knekelbeen_nek (Autodesk Fusion 360 design; units mm, degrees)
part number: 2026-10-25-00-56-09-742
part number: 2026-10-25-00-59-24-102
part number: 2026-10-25-00-59-58-262
part number: 2026-10-25-01-19-24-813
part number: 2026-10-25-01-20-03-116
part number: 2026-10-25-01-20-03-267
part number: 2026-10-25-01-20-03-368
part number: 2026-10-25-01-20-03-475
part number: 2026-10-25-01-20-03-508
part number: 2026-10-26-13-14-03-304
part number: 2026-10-26-13-14-24-246
Autodesk Fusion 360 part; units mm, degrees
sketch "Base outline" plane through (0, 0, 0) normal (0, 0, 1) x (1, 0, 0) in component "Base"
  circle A0 centre (0, 0) radius 52
  line L0 (0, -27) -> (81, -27)
  line L1 (81, -27) -> (81, 27)
  line L2 (81, 27) -> (0, 27)
  line L3 (0, 27) -> (0, -27)
extrude "Base plate" add sketch "Base outline" along normal blind 3 makes body 1 in component "Base"
ref_plane "WorkPlane1" through (0, 0, 3) normal (0, 0, 1) x (1, 0, 0) in component "Base"
sketch "Back wall" plane through (0, 0, 3) normal (0, 0, 1) x (1, 0, 0) in component "Base"
  line L0 (70.5, -13.9) -> (78, -13.9)
  line L1 (78, -13.9) -> (78, 24.6)
  line L2 (78, 24.6) -> (70.5, 24.6)
  line L3 (70.5, 24.6) -> (70.5, -13.9)
extrude "Back wall (1)" add sketch "Back wall" along normal blind 26.5 bodies 1 in component "Base"
ref_plane "WorkPlane2" through (0, 0, 17.5) normal (0, 0, 1) x (1, 0, 0) in component "Base"
sketch "Corbels" plane through (0, 0, 17.5) normal (0, 0, 1) x (1, 0, 0) in component "Base"
  line L0 (61, -11.9) -> (72, -11.9)
  line L1 (72, -11.9) -> (72, -6.2)
  line L2 (72, -6.2) -> (61, -6.2)
  line L3 (61, -6.2) -> (61, -11.9)
  line L4 (61, 16.9) -> (72, 16.9)
  line L5 (72, 16.9) -> (72, 22.6)
  line L6 (72, 22.6) -> (61, 22.6)
  line L7 (61, 22.6) -> (61, 16.9)
extrude "Corbels (1)" add sketch "Corbels" along normal blind 12 separate body makes body 2 at (68.3333, -6.2, 21.5) makes body 3 at (68.3333, 22.6, 21.5) in component "Base"
chamfer "45 deg underside" distance 9.5 angle 45 2 edges at (61, -9.05, 17.5) (61, 19.75, 17.5) tangent chain off on bodies 2 3 in component "Base"
combine "Join corbels" operation add target body 1 tool bodies 2 3 in component "Base"
ref_plane "WorkPlane3" through (0, 0, 29.5) normal (0, 0, 1) x (1, 0, 0) in component "Base"
sketch "M2 inserts servo tabs" plane through (0, 0, 29.5) normal (0, 0, 1) x (1, 0, 0) in component "Base"
  circle A0 centre (64, -8.5) radius 1.5
  circle A1 centre (64, 19.2) radius 1.5
  dimension "d23" = 3
  dimension "d24" = 3
  measures "d23" diameter of A0
  measures "d24" diameter of A1
extrude "M2 insert holes" cut sketch "M2 inserts servo tabs" against normal blind 4 bodies 1 in component "Base"
sketch "Lazy susan holes" plane through (0, 0, 0) normal (0, 0, 1) x (1, 0, 0) in component "Base"
  circle A0 centre (-29, -29) radius 2.25
  circle A1 centre (-29, 29) radius 2.25
  circle A2 centre (29, -29) radius 2.25
  circle A3 centre (29, 29) radius 2.25
extrude "Lazy susan holes (1)" cut sketch "Lazy susan holes" along normal blind 3 bodies 1 in component "Base"
sketch "Lazy susan countersinks" plane through (0, 0, 0) normal (0, 0, 1) x (1, 0, 0) in component "Base"
  circle A0 centre (-29, -29) radius 4.3
  circle A1 centre (-29, 29) radius 4.3
  circle A2 centre (29, -29) radius 4.3
  circle A3 centre (29, 29) radius 4.3
extrude "Countersinks M4" cut sketch "Lazy susan countersinks" along normal blind 2.05 draft -45 bodies 1 in component "Base"
sketch "Floor screw holes" plane through (0, 0, 0) normal (0, 0, 1) x (1, 0, 0) in component "Base"
  circle A0 centre (46.5, 0) radius 1.7
  circle A1 centre (-46.5, 0) radius 1.7
  circle A2 centre (0, 46.5) radius 1.7
  circle A3 centre (0, -46.5) radius 1.7
extrude "Floor screw holes (1)" cut sketch "Floor screw holes" along normal blind 3 bodies 1 in component "Base"
sketch "Floor screw countersinks" plane through (0, 0, 3) normal (0, 0, 1) x (1, 0, 0) in component "Base"
  circle A0 centre (46.5, 0) radius 3.3
  circle A1 centre (-46.5, 0) radius 3.3
  circle A2 centre (0, 46.5) radius 3.3
  circle A3 centre (0, -46.5) radius 3.3
extrude "Floor countersinks" cut sketch "Floor screw countersinks" against normal blind 1.6 draft -45 bodies 1 in component "Base"
sketch "Centre + arm screw access" plane through (0, 0, 0) normal (0, 0, 1) x (1, 0, 0) in component "Base"
  circle A0 centre (0, 0) radius 15
  circle A1 centre (64, 0) radius 3.5
extrude "Centre + access holes" cut sketch "Centre + arm screw access" along normal blind 3 bodies 1 in component "Base"
ref_plane "WorkPlane1" through (0, 0, 11) normal (0, 0, 1) x (1, 0, 0) in component "Cap"
ref_plane "WorkPlane2" through (0, 0, 15) normal (0, 0, 1) x (1, 0, 0) in component "Cap"
sketch "Cap outline" plane through (0, 0, 11) normal (0, 0, 1) x (1, 0, 0) in component "Cap"
  circle A0 centre (0, 0) radius 48
  line L0 (30, -7) -> (57, -7)
  line L1 (57, -7) -> (57, 7)
  line L2 (57, 7) -> (30, 7)
  line L3 (30, 7) -> (30, -7)
extrude "Cap plate" add sketch "Cap outline" along normal blind 4 separate body makes body 4 in component "Cap"
sketch "Wire hole" plane through (0, 0, 11) normal (0, 0, 1) x (1, 0, 0) in component "Cap"
  circle A0 centre (0, 0) radius 7
extrude "Wire hole (1)" cut sketch "Wire hole" along normal blind 4 bodies 4 in component "Cap"
sketch "Ball track clearance" plane through (0, 0, 11) normal (0, 0, 1) x (1, 0, 0) in component "Cap"
  circle A0 centre (0, 0) radius 34
  circle A1 centre (0, 0) radius 15
extrude "Ball track clearance (1)" cut sketch "Ball track clearance" along normal blind 1.5 bodies 4 in component "Cap"
sketch "Wire channel (side away from servo)" plane through (0, 0, 11) normal (0, 0, 1) x (1, 0, 0) in component "Cap"
  line L0 (-49, -4) -> (-6, -4)
  line L1 (-6, -4) -> (-6, 4)
  line L2 (-6, 4) -> (-49, 4)
  line L3 (-49, 4) -> (-49, -4)
extrude "Wire channel" cut sketch "Wire channel (side away from servo)" along normal blind 2 bodies 4 in component "Cap"
sketch "Pin slot" plane through (0, 0, 11) normal (0, 0, 1) x (1, 0, 0) in component "Cap"
  line L0 (28, -1.7) -> (53, -1.7)
  line L1 (53, -1.7) -> (53, 1.7)
  line L2 (53, 1.7) -> (28, 1.7)
  line L3 (28, 1.7) -> (28, -1.7)
  circle A0 centre (28, 0) radius 1.7
  circle A1 centre (53, 0) radius 1.7
extrude "Pin slot (1)" cut sketch "Pin slot" along normal blind 4 bodies 4 in component "Cap"
sketch "M4 inserts (to lazy susan top plate)" plane through (0, 0, 11) normal (0, 0, 1) x (1, 0, 0) in component "Cap"
  circle A0 centre (0, 41) radius 2.8
  circle A1 centre (-41, 0) radius 2.8
  circle A2 centre (0, -41) radius 2.8
  dimension "d51" = 5.6
  dimension "d52" = 5.6
  dimension "d53" = 5.6
  measures "d51" diameter of A0
  measures "d52" diameter of A1
  measures "d53" diameter of A2
extrude "M4 insert holes" cut sketch "M4 inserts (to lazy susan top plate)" along normal blind 4 bodies 4 in component "Cap"
sketch "Neck guide groove" plane through (0, 0, 0) normal (0, 1, 0) x (1, 0, 0) in component "Cap"
  line L0 (11.2, -15.01) -> (11.8, -14.4)
  line L1 (11.8, -14.4) -> (12.4, -15.01)
  line L2 (12.4, -15.01) -> (11.2, -15.01)
revolve "Neck guide groove (1)" cut sketch "Neck guide groove" angle 360 about axis through (0, 0, 1.75) along (0, 0, 1) bodies 4 in component "Cap"
sketch "Sketch1" plane through (0, 0, 25.5) normal (0, 0, 1) x (1, 0, 0)
  circle A0 centre (64, -8.5) radius 1.5
sketch "Servo posts (back half, outside arm sweep)" plane through (0, 0, 3) normal (0, 0, 1) x (1, 0, 0) in component "Base"
  line L0 (66.5, -11.9) -> (71, -11.9)
  line L1 (71, -11.9) -> (71, -6.2)
  line L2 (71, -6.2) -> (66.5, -6.2)
  line L3 (66.5, -6.2) -> (66.5, -11.9)
  line L4 (66.5, 16.9) -> (71, 16.9)
  line L5 (71, 16.9) -> (71, 22.6)
  line L6 (71, 22.6) -> (66.5, 22.6)
  line L7 (66.5, 22.6) -> (66.5, 16.9)
extrude "Servo posts to floor" add sketch "Servo posts (back half, outside arm sweep)" along normal blind 26.5 bodies 1 in component "Base"
ref_plane "WorkPlane1" through (0, 0, 20.5) normal (0, 0, 1) x (1, 0, 0) in component "Servo arm"
ref_plane "WorkPlane2" through (0, 0, 16.5) normal (0, 0, 1) x (1, 0, 0) in component "Servo arm"
ref_plane "WorkPlane3" through (0, 0, 11.5) normal (0, 0, 1) x (1, 0, 0) in component "Servo arm"
ref_plane "WorkPlane4" through (0, 0, 16) normal (0, 0, 1) x (1, 0, 0) in component "Servo arm"
sketch "Arm outline" plane through (0, 0, 16.5) normal (0, 0, 1) x (1, 0, 0) in component "Servo arm"
  circle A0 centre (64, 0) radius 5.5
  line L0 (31, -4.5) -> (64, -4.5)
  line L1 (64, -4.5) -> (64, 4.5)
  line L2 (64, 4.5) -> (31, 4.5)
  line L3 (31, 4.5) -> (31, -4.5)
  circle A1 centre (31, 0) radius 4.5
extrude "Arm" add sketch "Arm outline" along normal blind 4 separate body makes body 5 in component "Servo arm"
sketch "Hub" plane through (0, 0, 11.5) normal (0, 0, 1) x (1, 0, 0) in component "Servo arm"
  circle A0 centre (64, 0) radius 5.5
extrude "Hub (1)" add sketch "Hub" along normal blind 5 bodies 5 in component "Servo arm"
sketch "Spline bore" plane through (0, 0, 20.5) normal (0, 0, 1) x (1, 0, 0) in component "Servo arm"
  circle A0 centre (64, 0) radius 2.4
  dimension "d71" = 4.8
  measures "d71" diameter of A0
extrude "Spline bore (1)" cut sketch "Spline bore" against normal blind 4.5 bodies 5 in component "Servo arm"
sketch "Bore end 45 deg" plane through (0, 0, 16) normal (0, 0, 1) x (1, 0, 0) in component "Servo arm"
  circle A0 centre (64, 0) radius 2.4
  dimension "d74" = 4.8
  measures "d74" diameter of A0
extrude "Bore end 45 deg (1)" cut sketch "Bore end 45 deg" against normal blind 1.25 draft -45 bodies 5 in component "Servo arm"
sketch "Horn screw" plane through (0, 0, 11.5) normal (0, 0, 1) x (1, 0, 0) in component "Servo arm"
  circle A0 centre (64, 0) radius 1.15
extrude "Horn screw hole" cut sketch "Horn screw" along normal blind 4.5 bodies 5 in component "Servo arm"
sketch "Horn screw head" plane through (0, 0, 11.5) normal (0, 0, 1) x (1, 0, 0) in component "Servo arm"
  circle A0 centre (64, 0) radius 2.3
extrude "Horn screw head (1)" cut sketch "Horn screw head" along normal blind 2 bodies 5 in component "Servo arm"
sketch "M3 insert (pin)" plane through (0, 0, 16.5) normal (0, 0, 1) x (1, 0, 0) in component "Servo arm"
  circle A0 centre (31, 0) radius 2.1
  dimension "d81" = 4.2
  measures "d81" diameter of A0
extrude "M3 insert hole" cut sketch "M3 insert (pin)" along normal blind 4 bodies 5 in component "Servo arm"
ref_plane "WorkPlane1" through (0, 0, 3) normal (0, 0, 1) x (1, 0, 0) in component "REF Lazy susan bottom (fixed)"
sketch "Bottom plate" plane through (0, 0, 3) normal (0, 0, 1) x (1, 0, 0) in component "REF Lazy susan bottom (fixed)"
  line L0 (36, 26) -> (35.6593, 28.5882)
  line L1 (35.6593, 28.5882) -> (34.6603, 31)
  line L2 (34.6603, 31) -> (33.0711, 33.0711)
  line L3 (33.0711, 33.0711) -> (31, 34.6603)
  line L4 (31, 34.6603) -> (28.5882, 35.6593)
  line L5 (28.5882, 35.6593) -> (26, 36)
  line L6 (26, 36) -> (-26, 36)
  line L7 (-26, 36) -> (-28.5882, 35.6593)
  line L8 (-28.5882, 35.6593) -> (-31, 34.6603)
  line L9 (-31, 34.6603) -> (-33.0711, 33.0711)
  line L10 (-33.0711, 33.0711) -> (-34.6603, 31)
  line L11 (-34.6603, 31) -> (-35.6593, 28.5882)
  line L12 (-35.6593, 28.5882) -> (-36, 26)
  line L13 (-36, 26) -> (-36, -26)
  line L14 (-36, -26) -> (-35.6593, -28.5882)
  line L15 (-35.6593, -28.5882) -> (-34.6603, -31)
  line L16 (-34.6603, -31) -> (-33.0711, -33.0711)
  line L17 (-33.0711, -33.0711) -> (-31, -34.6603)
  line L18 (-31, -34.6603) -> (-28.5882, -35.6593)
  line L19 (-28.5882, -35.6593) -> (-26, -36)
  line L20 (-26, -36) -> (26, -36)
  line L21 (26, -36) -> (28.5882, -35.6593)
  line L22 (28.5882, -35.6593) -> (31, -34.6603)
  line L23 (31, -34.6603) -> (33.0711, -33.0711)
  line L24 (33.0711, -33.0711) -> (34.6603, -31)
  line L25 (34.6603, -31) -> (35.6593, -28.5882)
  line L26 (35.6593, -28.5882) -> (36, -26)
  line L27 (36, -26) -> (36, 26)
  circle A0 centre (0, 0) radius 17
  circle A1 centre (-29, -29) radius 2.25
  circle A2 centre (-29, 29) radius 2.25
  circle A3 centre (29, -29) radius 2.25
  circle A4 centre (29, 29) radius 2.25
extrude "Extrude1" add sketch "Bottom plate" along normal blind 1 separate body makes body 6 in component "REF Lazy susan bottom (fixed)"
ref_plane "WorkPlane2" through (0, 0, 4) normal (0, 0, 1) x (1, 0, 0) in component "REF Lazy susan bottom (fixed)"
sketch "Ball track" plane through (0, 0, 4) normal (0, 0, 1) x (1, 0, 0) in component "REF Lazy susan bottom (fixed)"
  circle A0 centre (0, 0) radius 31
  circle A1 centre (0, 0) radius 18
extrude "Extrude2" add sketch "Ball track" along normal blind 6 separate body makes body 7 in component "REF Lazy susan bottom (fixed)"
ref_plane "WorkPlane1" through (0, 0, 10) normal (0, 0, 1) x (1, 0, 0) in component "REF Lazy susan top (turns)"
sketch "Top plate" plane through (0, 0, 10) normal (0, 0, 1) x (1, 0, 0) in component "REF Lazy susan top (turns)"
  line L0 (7.0711, 43.8406) -> (5, 45.4298)
  line L1 (5, 45.4298) -> (2.5882, 46.4288)
  line L2 (2.5882, 46.4288) -> (0, 46.7696)
  line L3 (0, 46.7696) -> (-2.5882, 46.4288)
  line L4 (-2.5882, 46.4288) -> (-5, 45.4298)
  line L5 (-5, 45.4298) -> (-7.0711, 43.8406)
  line L6 (-7.0711, 43.8406) -> (-43.8406, 7.0711)
  line L7 (-43.8406, 7.0711) -> (-45.4298, 5)
  line L8 (-45.4298, 5) -> (-46.4288, 2.5882)
  line L9 (-46.4288, 2.5882) -> (-46.7696, 0)
  line L10 (-46.7696, 0) -> (-46.4288, -2.5882)
  line L11 (-46.4288, -2.5882) -> (-45.4298, -5)
  line L12 (-45.4298, -5) -> (-43.8406, -7.0711)
  line L13 (-43.8406, -7.0711) -> (-7.0711, -43.8406)
  line L14 (-7.0711, -43.8406) -> (-5, -45.4298)
  line L15 (-5, -45.4298) -> (-2.5882, -46.4288)
  line L16 (-2.5882, -46.4288) -> (0, -46.7696)
  line L17 (0, -46.7696) -> (2.5882, -46.4288)
  line L18 (2.5882, -46.4288) -> (5, -45.4298)
  line L19 (5, -45.4298) -> (7.0711, -43.8406)
  line L20 (7.0711, -43.8406) -> (43.8406, -7.0711)
  line L21 (43.8406, -7.0711) -> (45.4298, -5)
  line L22 (45.4298, -5) -> (46.4288, -2.5882)
  line L23 (46.4288, -2.5882) -> (46.7696, 0)
  line L24 (46.7696, 0) -> (46.4288, 2.5882)
  line L25 (46.4288, 2.5882) -> (45.4298, 5)
  line L26 (45.4298, 5) -> (43.8406, 7.0711)
  line L27 (43.8406, 7.0711) -> (7.0711, 43.8406)
  circle A0 centre (0, 0) radius 17
  circle A1 centre (41, 0) radius 2.25
  circle A2 centre (0, 41) radius 2.25
  circle A3 centre (-41, 0) radius 2.25
  circle A4 centre (0, -41) radius 2.25
extrude "Extrude1'" add sketch "Top plate" along normal blind 1 separate body makes body 8 in component "REF Lazy susan top (turns)"
ref_plane "WorkPlane1" through (0, 0, 25) normal (0, 0, 1) x (1, 0, 0) in component "REF Servo"
sketch "Body" plane through (0, 0, 25) normal (0, 0, 1) x (1, 0, 0) in component "REF Servo"
  line L0 (58.05, -6) -> (69.95, -6)
  line L1 (69.95, -6) -> (69.95, 16.7)
  line L2 (69.95, 16.7) -> (58.05, 16.7)
  line L3 (58.05, 16.7) -> (58.05, -6)
extrude "Body (1)" add sketch "Body" along normal blind 23 separate body makes body 9 in component "REF Servo"
ref_plane "WorkPlane2" through (0, 0, 29.5) normal (0, 0, 1) x (1, 0, 0) in component "REF Servo"
sketch "Tabs" plane through (0, 0, 29.5) normal (0, 0, 1) x (1, 0, 0) in component "REF Servo"
  line L0 (58.55, -10.9) -> (69.45, -10.9)
  line L1 (69.45, -10.9) -> (69.45, 21.6)
  line L2 (69.45, 21.6) -> (58.55, 21.6)
  line L3 (58.55, 21.6) -> (58.55, -10.9)
extrude "Tabs (1)" add sketch "Tabs" along normal blind 2.5 bodies 9 in component "REF Servo"
ref_plane "WorkPlane3" through (0, 0, 20.5) normal (0, 0, 1) x (1, 0, 0) in component "REF Servo"
sketch "Output boss" plane through (0, 0, 20.5) normal (0, 0, 1) x (1, 0, 0) in component "REF Servo"
  circle A0 centre (64, 0) radius 3
extrude "Output boss (1)" add sketch "Output boss" along normal blind 4.5 bodies 9 in component "REF Servo"
ref_plane "WorkPlane4" through (0, 0, 17) normal (0, 0, 1) x (1, 0, 0) in component "REF Servo"
sketch "Spline" plane through (0, 0, 17) normal (0, 0, 1) x (1, 0, 0) in component "REF Servo"
  circle A0 centre (64, 0) radius 2.35
extrude "Spline (1)" add sketch "Spline" along normal blind 3.5 separate body makes body 10 in component "REF Servo"
ref_plane "WorkPlane1" through (0, 0, 11.5) normal (0, 0, 1) x (1, 0, 0) in component "REF Pin (M3x10 set screw)"
sketch "Pin" plane through (0, 0, 11.5) normal (0, 0, 1) x (1, 0, 0) in component "REF Pin (M3x10 set screw)"
  circle A0 centre (31, 0) radius 1.5
extrude "Extrude1''" add sketch "Pin" along normal blind 9 separate body makes body 11 in component "REF Pin (M3x10 set screw)"
ref_plane "WorkPlane1" through (0, 0, 35.5) normal (0, 0, 1) x (1, 0, 0) in component "REF Skull neck 23 mm"
sketch "Neck" plane through (0, 0, 35.5) normal (0, 0, 1) x (1, 0, 0) in component "REF Skull neck 23 mm"
  circle A0 centre (0, 0) radius 11.5
  circle A1 centre (0, 0) radius 7.5
extrude "Extrude1'''" add sketch "Neck" along normal blind 25 separate body makes body 12 in component "REF Skull neck 23 mm"
sketch "Access hole (wood screws of lazy susan)" plane through (0, 0, 11) normal (0, 0, 1) x (1, 0, 0) in component "Cap"
  circle A0 centre (28.9914, 28.9914) radius 4.5
extrude "Access hole" cut sketch "Access hole (wood screws of lazy susan)" along normal blind 4 bodies 4 in component "Cap"
sketch "Bore entry chamfer" plane through (0, 0, 20.5) normal (0, 0, 1) x (1, 0, 0) in component "Servo arm"
  circle A0 centre (64, 0) radius 2.9
  dimension "d122" = 5.8
  measures "d122" diameter of A0
extrude "Bore entry chamfer (1)" cut sketch "Bore entry chamfer" against normal blind 0.5 draft -45 bodies 5 in component "Servo arm"
ref_plane "WorkPlane1" through (0, 0, 15) normal (0, 0, 1) x (1, 0, 0) in component "Disc spacer"
ref_plane "WorkPlane2" through (0, 0, 22) normal (0, 0, 1) x (1, 0, 0) in component "Disc spacer"
ref_plane "WorkPlane3" through (0, 0, 28) normal (0, 0, 1) x (1, 0, 0) in component "Disc spacer"
sketch "Column" plane through (0, 0, 15) normal (0, 0, 1) x (1, 0, 0) in component "Disc spacer"
  circle A0 centre (0, 0) radius 24
extrude "Column (1)" add sketch "Column" along normal blind 7 separate body makes body 13 in component "Disc spacer"
sketch "Flare" plane through (0, 0, 22) normal (0, 0, 1) x (1, 0, 0) in component "Disc spacer"
  circle A0 centre (0, 0) radius 24
extrude "Flare 45 deg" add sketch "Flare" along normal blind 6 draft 45 bodies 13 in component "Disc spacer"
sketch "Glue face" plane through (0, 0, 28) normal (0, 0, 1) x (1, 0, 0) in component "Disc spacer"
  circle A0 centre (0, 0) radius 30
extrude "Glue face (1)" add sketch "Glue face" along normal blind 1.5 bodies 13 in component "Disc spacer"
sketch "Wire bore" plane through (0, 0, 15) normal (0, 0, 1) x (1, 0, 0) in component "Disc spacer"
  circle A0 centre (0, 0) radius 7
extrude "Wire bore (1)" cut sketch "Wire bore" along normal blind 14.5 bodies 13 in component "Disc spacer"
sketch "Centring ridge" plane through (0, 0, 0) normal (0, 1, 0) x (1, 0, 0) in component "Disc spacer"
  line L0 (11.3, -15.01) -> (11.8, -14.5)
  line L1 (11.8, -14.5) -> (12.3, -15.01)
  line L2 (12.3, -15.01) -> (11.3, -15.01)
revolve "Centring ridge (1)" add sketch "Centring ridge" angle 360 about axis through (0, 0, 1.75) along (0, 0, 1) bodies 13 in component "Disc spacer"
ref_plane "WorkPlane1" through (0, 0, 29.5) normal (0, 0, 1) x (1, 0, 0) in component "REF Wood disc"
sketch "Disc" plane through (0, 0, 29.5) normal (0, 0, 1) x (1, 0, 0) in component "REF Wood disc"
  circle A0 centre (0, 0) radius 40
  circle A1 centre (0, 0) radius 7
extrude "Extrude1''''" add sketch "Disc" along normal blind 6 separate body contours A0 | A1 makes body 14 in component "REF Wood disc"
component "Base" placed x (1, 0, 0) y (0, 1, 0) z (0, 0, 1) at (0, 0, 0)
component "Cap" placed x (1, 0, 0) y (0, 1, 0) z (0, 0, 1) at (0, 0, 0)
component "Servo arm" placed x (1, 0, 0) y (0, 1, 0) z (0, 0, 1) at (0, 0, 0)
component "REF Lazy susan bottom (fixed)" placed x (1, 0, 0) y (0, 1, 0) z (0, 0, 1) at (0, 0, 0)
component "REF Lazy susan top (turns)" placed x (1, 0, 0) y (0, 1, 0) z (0, 0, 1) at (0, 0, 0)
component "REF Servo" placed x (1, 0, 0) y (0, 1, 0) z (0, 0, 1) at (0, 0, 0)
component "REF Pin (M3x10 set screw)" placed x (1, 0, 0) y (0, 1, 0) z (0, 0, 1) at (0, 0, 0)
component "REF Skull neck 23 mm" placed x (1, 0, 0) y (0, 1, 0) z (0, 0, 1) at (0, 0, 0)
component "Disc spacer" placed x (1, 0, 0) y (0, 1, 0) z (0, 0, 1) at (0, 0, 0)
component "REF Wood disc" placed x (1, 0, 0) y (0, 1, 0) z (0, 0, 1) at (0, 0, 0)
equation "base_t = 3 mm" comment "base plate thickness"
equation "brg_h = 8 mm" comment "lazy susan height"
equation "cap_t = 4 mm" comment "cap thickness (neck glues on top)"
equation "tab_z = 29.5 mm" comment "top of the corbels = where the servo tabs rest (servo hangs upside down)"
equation "arm_t = 4 mm" comment "servo arm thickness"
equation "ins_m2 = 3.0 mm" comment "hole for M2x3x3.2 insert (servo tabs)"
equation "ins_m3 = 4.2 mm" comment "hole for M3x4x5 insert (pin set screw in the arm)"
equation "ins_m4 = 5.6 mm" comment "hole for M4x4x6 insert (cap to lazy susan top plate)"
equation "spline_d = 4.8 mm" comment "servo spline bore (press fit)"
equation "d10 = base_t"
equation "d12 = base_t"
equation "d14 = tab_z - base_t"
equation "d16 = tab_z - 12 mm"
equation "d21 = tab_z"
equation "d23 = ins_m2"
equation "d24 = ins_m2"
equation "d25 = -( 4 mm )"
equation "d27 = base_t"
equation "d31 = base_t"
equation "d33 = -( 1.6 mm )"
equation "d35 = base_t"
equation "d37 = base_t + brg_h"
equation "d39 = base_t + brg_h + cap_t"
equation "d41 = cap_t"
equation "d43 = cap_t"
equation "d49 = cap_t"
equation "d51 = ins_m4"
equation "d52 = ins_m4"
equation "d53 = ins_m4"
equation "d54 = cap_t"
equation "d57 = tab_z - base_t"
equation "d59 = tab_z - 9 mm"
equation "d61 = tab_z - 9 mm - arm_t"
equation "d63 = tab_z - 18 mm"
equation "d65 = tab_z - 13.5 mm"
equation "d67 = arm_t"
equation "d69 = 9 mm - arm_t"
equation "d71 = spline_d"
equation "d72 = -( 4.5 mm )"
equation "d74 = spline_d"
equation "d75 = -( 1.25 mm )"
equation "d81 = ins_m3"
equation "d82 = arm_t"
equation "d84 = base_t"
equation "d88 = base_t + 1 mm"
equation "d90 = brg_h - 2 mm"
equation "d92 = base_t + brg_h - 1 mm"
equation "d96 = tab_z - 4.5 mm"
equation "d100 = tab_z"
equation "d104 = tab_z - 9 mm"
equation "d108 = tab_z - 12.5 mm"
equation "d112 = base_t + brg_h + 0.5 mm"
equation "d116 = tab_z + plank_t"
equation "d120 = cap_t"
equation "d122 = spline_d + 1 mm"
equation "d123 = -( 0.5 mm )"
equation "d125 = base_t + brg_h + cap_t"
equation "d127 = tab_z - 7.5 mm"
equation "d129 = tab_z - 1.5 mm"
equation "d131 = tab_z - base_t - brg_h - cap_t - 7.5 mm"
equation "d137 = tab_z - base_t - brg_h - cap_t"
equation "plank_t = 6 mm" comment "thickness of the wooden floor plank (only moves the reference parts)"
equation "d143 = tab_z"
equation "d145 = plank_t"
named bodies: "Base", "Cap", "Servo arm", "Bottom plate", "Ball track", "Top plate", "Servo", "Spline", "Pin", "Neck", "Disc spacer", "Wood disc (80 mm shown)"
